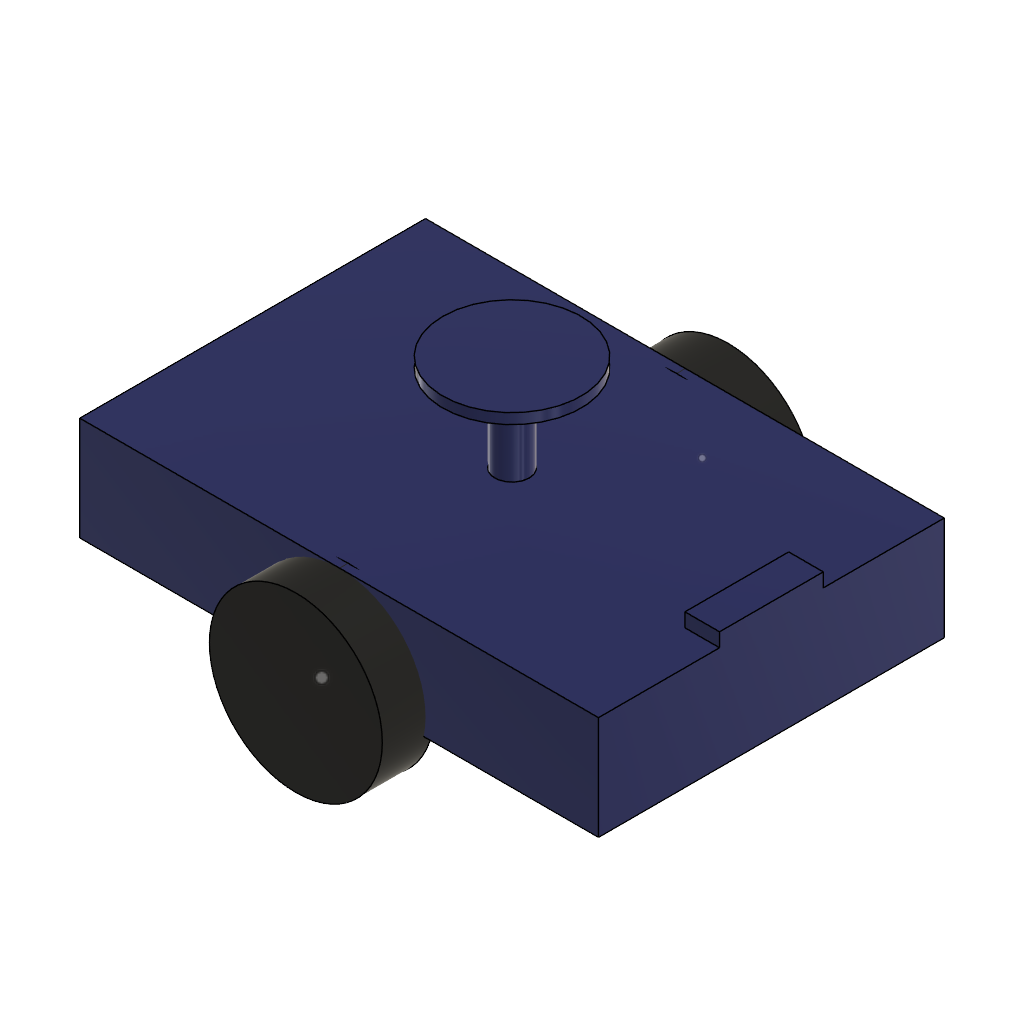
my_robot (Autodesk Fusion 360 design; units mm, degrees)
part number: 2026-10-27-11-33-50-809
part number: 2026-10-27-11-33-54-647
part number: 2026-10-27-11-33-55-089
part number: 2026-10-27-11-33-55-183
part number: 2026-10-27-11-33-55-288
Autodesk Fusion 360 part; units mm, degrees
ref_plane "WorkPlane1" through (0, 0, 20) normal (0, 0, 1) x (1, 0, 0) in component "base_link"
sketch "Chassis outline" plane through (0, 0, 20) normal (0, 0, 1) x (1, 0, 0) in component "base_link"
  line L0 (-150, -100) -> (150, -100)
  line L1 (150, -100) -> (150, 100)
  line L2 (150, 100) -> (-150, 100)
  line L3 (-150, 100) -> (-150, -100)
extrude "Chassis 300x200x60" add sketch "Chassis outline" along normal mid plane 60 makes body 1 in component "base_link"
ref_plane "WorkPlane2" through (0, 0, 75) normal (0, 0, 1) x (1, 0, 0) in component "base_link"
sketch "LiDAR post" plane through (0, 0, 75) normal (0, 0, 1) x (1, 0, 0) in component "base_link"
  circle A0 centre (0, 0) radius 10
extrude "LiDAR post (1)" add sketch "LiDAR post" along normal mid plane 50 bodies 1 in component "base_link"
ref_plane "WorkPlane3" through (0, 0, 103) normal (0, 0, 1) x (1, 0, 0) in component "base_link"
sketch "LiDAR plate (mount z=0.11 m)" plane through (0, 0, 103) normal (0, 0, 1) x (1, 0, 0) in component "base_link"
  circle A0 centre (0, 0) radius 40
extrude "LiDAR plate" add sketch "LiDAR plate (mount z=0.11 m)" along normal mid plane 6 bodies 1 in component "base_link"
ref_plane "WorkPlane1" through (0, 110, 0) normal (0, 1, 0) x (0, 0, 1) in component "left_wheel"
sketch "left_wheel profile" plane through (0, 110, 0) normal (0, 1, 0) x (1, 0, 0) in component "left_wheel"
  circle A0 centre (0, 0) radius 50
extrude "left_wheel 100x30" add sketch "left_wheel profile" along normal mid plane 30 separate body makes body 2 in component "left_wheel"
ref_plane "WorkPlane1" through (0, -110, 0) normal (0, 1, 0) x (0, 0, 1) in component "right_wheel"
sketch "right_wheel profile" plane through (0, -110, 0) normal (0, 1, 0) x (1, 0, 0) in component "right_wheel"
  circle A0 centre (0, 0) radius 50
extrude "right_wheel 100x30" add sketch "right_wheel profile" along normal mid plane 30 separate body makes body 3 in component "right_wheel"
sketch "Caster profile" plane through (0, 0, 0) normal (0, 1, 0) x (1, 0, 0) in component "caster"
  line L0 (-120, 0) -> (-120, 50)
  arc A0 (-120, 0) -> (-120, 50) centre (-120, 25) ccw
revolve "Caster sphere 50" add sketch "Caster profile" angle 360 about axis through (-120, 0, 0) along (0, 0, -1) separate body makes body 4 in component "caster"
sketch "left_wheel joint origin" plane through (0, 0, 0) normal (0, 1, 0) x (1, 0, 0) in component "left_wheel"
sketch "right_wheel joint origin" plane through (0, 0, 0) normal (0, 1, 0) x (1, 0, 0) in component "right_wheel"
ref_plane "WorkPlane5" through (0, 0, 54) normal (0, 0, 1) x (1, 0, 0) in component "base_link"
sketch "Camera mount plate (front x=0.14 m)" plane through (0, 0, 54) normal (0, 0, 1) x (1, 0, 0) in component "base_link"
  line L0 (130, -30) -> (150, -30)
  line L1 (150, -30) -> (150, 30)
  line L2 (150, 30) -> (130, 30)
  line L3 (130, 30) -> (130, -30)
extrude "Camera mount" add sketch "Camera mount plate (front x=0.14 m)" along normal mid plane 8 bodies 1 in component "base_link"
component "base_link" placed x (1, 0, 0) y (0, 1, 0) z (0, 0, 1) at (0, 0, 0)
component "left_wheel" placed x (1, 0, 0) y (0, 1, 0) z (0, 0, 1) at (0, 0, 0)
component "right_wheel" placed x (1, 0, 0) y (0, 1, 0) z (0, 0, 1) at (0, 0, 0)
component "caster" placed x (1, 0, 0) y (0, 1, 0) z (0, 0, 1) at (0, 0, 0)
equation "wheel_radius = 50 mm" comment "Wheel radius"
equation "wheel_width = 30 mm" comment "Wheel width"
equation "wheel_separation = 220 mm" comment "Wheel separation"
equation "chassis_x = 300 mm" comment "Chassis length"
equation "chassis_y = 200 mm" comment "Chassis width"
equation "chassis_z = 60 mm" comment "Chassis height"
named bodies: "base_link body", "left_wheel body", "right_wheel body", "caster body"
